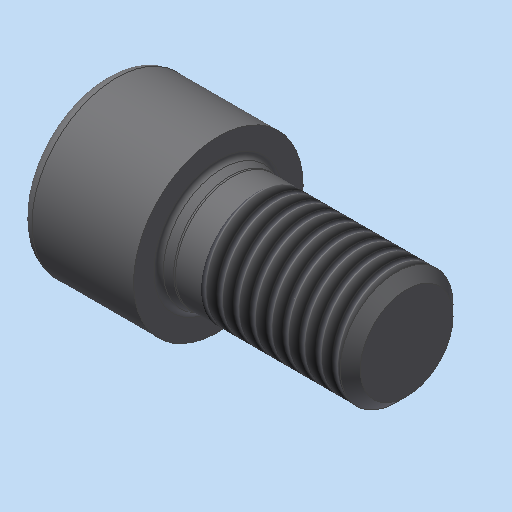
# Autodesk Inventor part: Zylinderschraube_ISO_4762___M12x20
Saved by Autodesk Inventor 2023.3 (Build 273359000, 359)
## iProperties
Shininess: 64.0
Length Units: 11269
Angle Units: 11279
Time Units: 11290
Mass Units: 11283
Length Display Precision: 3
Angle Display Precision: 2
Compacted: True
Part Number: Zylinderschraube_ISO_4762___M12x20
Document SubType Name: Modeling
Created: 2004-04-03
Material: xStahl_AnP_Dummymaterial
Description: =<RBPARTNOTITLE2>
Vendor: NORM8
Designer: S.Riedelsheimer
Manufacturer: Standard
Standards Organization: Custom
Density: 7.85 g/cm^3
Appearance: Stahl - normal AnP
Mass: 36.0052 g
Surface Area: 21.2241 cm^2
Volume: 4.58665 cm^3
Density: 0.0
Volumn: 0.0
Area: 0.0
PropertySet Name: Model Information
Control State: 0
Master: False
Checked Out: False
CNS_NB: Zylinderschraube ISO 4762 - M12x20
CNS_NN: ISO 4762
CNS_NT: Zylinderschrauben mit Innensechskant
CNS_NBSYN: Zylinderschraube ISO 4762 - $NENN.
CNS_LINA: Zylinderschraube ISO 4762 - M12x20
CNS_D: 12.000
CNS_D3: 9.853
CNS_P: 1.750
CNS_L: 20.000
CNS_S: 10.000
CNS_HM: 20.000
CNS_DK: 18.000
CNS_DA: 13.700
CNS_DS: 12.000
CNS_E: 11.430
CNS_K: 12.000
CNS_R: 0.600
CNS_T: 6.000
CNS_V: 1.200
CNS_DW: 17.230
CNS_W: 4.800
CNS_LF: 1.450
CNS_LG: 5.250
CNS_FORM: 1.000
CNS_NENN: M12x20
CNS_KT: DUMMY
PSOL_IDENT_0: {C:\partsolutions8\data\23d-libs\bosch_bamberg\schrauben\zylinderschrauben\din_en_iso_4762.prj},171
PSOL_IDENT_1: {M=Nenngewinde},{VTYP=3D},{NB=Zylinderschraube ISO 4762 - M12x20},{NN=ISO 4762},{DATE=26.11.2003},{G
PSOL_IDENT_2: EOMDATE=26.11.2003},{VERSION=v2},{LINEID=990},{LINESUBID=-1},{WBVAR=}  {NB=Zylinderschraube ISO 4762
PSOL_IDENT_3: - M12x20},{LINA=Zylinderschraube ISO 4762 - M12x20},{KT=DUMMY},{IDNR=},{D=12.000},{D3=9.853},{P=1.7
PSOL_IDENT_4: 50},{L=20.000},{S=10.000},{HM=20.000},{DK=18.000},{DA=13.700},{DS=12.000},{E=11.430},{K=12.000},{R=0
PSOL_IDENT_5: .600},{T=6.000},{V=1.200},{DW=17.230},{W=4.800},{LF=1.450},{LG=5.250},{FORM=1.000},{NENN=M12x20}
RBPARTNOTITLE2: Zylinderschrauben mit Innensechskant
RBPARTNOTITLE1: Hexagon socket head cap screws
AnP_Kategorie: 4
RBDRAWINGMISSINGSPEC: --
RBPARTMADEOF: ISO 4762 - M12x20 - 8.8 verzinkt
Title: Zylinderschraube ISO 4762 - M12x20
Author: S.Riedelsheimer
Keywords: =<RBPARTMADEOF>
Comments: =<RBSURFACE2>
Revision Number: 01
Autodesk Inventor part; units mm, degrees
sketch "Skizze_2" plane through (0, 0, 0) normal (0, 0, 1) x (1, 0, 0)
  line L0 (23, 0) -> (-15, 0)
  line L1 (-1.9132, 0) -> (-4.8, 5)
  line L2 (-4.8, 5) -> (-11.285, 5)
  line L3 (-11.285, 5) -> (-12, 5.715)
  line L4 (-12, 5.715) -> (-12, 7.8)
  arc A0 (-10.8, 9) -> (-12, 7.8) centre (-10.8, 7.8) ccw
  line L5 (-10.8, 9) -> (0, 9)
  line L6 (0, 9) -> (0, 6.85)
  arc A1 (0, 6.85) -> (0.4307, 6.2744) centre (0.6, 6.85) ccw
  line L7 (0.4307, 6.2744) -> (1.2807, 6.0244)
  arc A2 (1.2807, 6.0244) -> (1.45, 6) centre (1.45, 6.6) ccw
  line L8 (1.45, 6) -> (18.9265, 6)
  line L9 (18.9265, 6) -> (20, 4.9265)
  line L10 (20, 4.9265) -> (20, 0)
  line L11 (20, 0) -> (-1.9132, 0)
  constraints: 24 end point, 6 point on circle, 3 centre point
revolve "Drehung1" add sketch "Skizze_2" angle 360 about axis through (23, 0, 0) along (1, 0, 0)
thread "Gewinde1" size "M12x1.75" class "6g" standard "ANSI Metric M Profile" length 14.75
sketch "Skizze_1" plane through (-4.8, 0, 0) normal (1, 0, 0) x (0, 0, -1)
  line L0 (-5, 2.8868) -> (-5, -2.8868)
  line L1 (-5, -2.8868) -> (0, -5.7735)
  line L2 (0, -5.7735) -> (5, -2.8868)
  line L3 (5, -2.8868) -> (5, 2.8868)
  line L4 (5, 2.8868) -> (0, 5.7735)
  line L5 (0, 5.7735) -> (-5, 2.8868)
  constraints: 12 end point
extrude "Extrusion1" cut sketch "Skizze_1" against normal blind 12
ref_plane "IP1_XY" through (0, 0, 0) normal (1, 0, 0) x (0, 0, -1)
ref_plane "IP1_YZ" through (0, 0, 0) normal (0, 0, -1) x (0, 1, 0)
ref_plane "IP3_XY" through (20, 0, 0) normal (1, 0, 0) x (0, 0, -1)
ref_plane "IP3_YZ" through (20, 0, 0) normal (0, 0, -1) x (0, 1, 0)
ref_plane "IP2_XY" through (-12, 0, 0) normal (1, 0, 0) x (0, 0, -1)
ref_plane "IP2_YZ" through (-12, 0, 0) normal (0, 0, -1) x (0, 1, 0)
